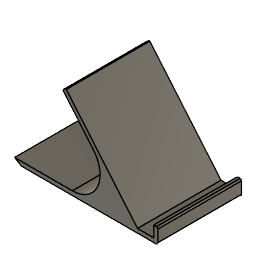
phone_holder_v01 (Autodesk Fusion 360 design; units mm, degrees)
part number: 2026-06-27-12-28-36-362
Autodesk Fusion 360 part; units mm, degrees
sketch "Sketch1" plane through (0, 0, 0) normal (0, 1, 0) x (1, 0, 0)
  line L0 (30, 0) -> (30, -8)
  line L1 (18.3095, 0) -> (-32.7921, -60.9005)
  line L2 (18.3095, 0) -> (98.3095, 0) construction
  line L3 (31.5, 3) -> (-65, 3)
  line L4 (33, 1.5) -> (33, -7)
  line L5 (30, -8) -> (32, -8)
  line L6 (-13.176, -32.8558) -> (-35.0902, -58.9722)
  line L7 (-35.0286, -59.6766) -> (-33.4965, -60.9622)
  line L8 (-70, 0) -> (-65, 3)
  arc A0 (33, 1.5) -> (31.5, 3) centre (31.5, 1.5) ccw
  arc A1 (32, -8) -> (33, -7) centre (32, -7) ccw
  line L9 (30, 0) -> (18.3095, 0)
  line L10 (-28.4969, 0) -> (-70, 0)
  arc A2 (-33.4965, -60.9622) -> (-32.7921, -60.9005) centre (-33.1751, -60.5791) ccw
  arc A3 (-35.0902, -58.9722) -> (-35.0286, -59.6766) centre (-34.7072, -59.2936) ccw
  arc A4 (-13.176, -32.8558) -> (-28.4969, 0) centre (-28.4969, -20) ccw
  point P0 (-33.1135, -61.2836)
  dimension "d1" = 100
  dimension "d2" = 8
  dimension "d3" = 130
  dimension "d4" = 80
  dimension "d7" = 1.5
  dimension "d8" = 1
  dimension "d9" = 0.5
  dimension "d10" = 0.5
  dimension "d11" = 20
  constraint horizontal L9
  constraint perpendicular L0 L9
  constraint horizontal L2
  constraint perpendicular L4 L5
  constraint perpendicular L1 L7
  constraint tangent L3 A0
  constraint tangent L4 A0
  constraint tangent L4 A1
  constraint tangent L5 A1
  constraint collinear L9 L10
  constraint coincident P0 L1
  constraint coincident P0 L7
  constraint tangent L1 A2
  constraint tangent L7 A2
  constraint tangent L6 A3
  constraint tangent L7 A3
  constraint tangent L10 A4
  constraint tangent L6 A4
  measures "d1" distance of L0.start L8.start
  measures "d2" distance of L0.start L0.end
  measures "d3" angle of L1 L2
  measures "d4" distance of L1.start P0
  measures "d7" radius of A0
  measures "d8" radius of A1
  measures "d9" radius of A2
  measures "d10" radius of A3
  measures "d11" radius of A4
extrude "Extrude1" add sketch "Sketch1" along normal blind 60
